Autodesk Fusion 360 part; units mm, degrees
(part 2 of 2)
extrude "124.5 mm pitch fan fixing clearance (3)" cut sketch "草图6 (8)" along normal blind 6 contours A0 in plane through (0, -25, 0) normal (0, 1, 0) bodies 20 in component "10_GPU_140_FAN_MOUNT"
ref_plane "工作平面1" through (0, 25, 0) normal (0, 1, 0) x (0, 0, 1) in component "10_CPU_140_FAN_MOUNT"
sketch "草图1 (21)" plane through (0, 25, 0) normal (0, 1, 0) x (1, 0, 0) in component "10_CPU_140_FAN_MOUNT"
  line L0 (156.4, -210, -50) -> (296.4, -210, -50)
  line L1 (296.4, -210, -50) -> (296.4, -350, -50)
  line L2 (296.4, -350, -50) -> (156.4, -350, -50)
  line L3 (156.4, -350, -50) -> (156.4, -210, -50)
extrude "140 mm removable fan mounting frame'" add sketch "草图1 (21)" along normal blind 6 separate body contours L0 L1 L2 L3 in plane through (0, -25, 0) normal (0, 1, 0) makes body 21 in component "10_CPU_140_FAN_MOUNT"
ref_plane "工作平面2" through (0, 25, 0) normal (0, 1, 0) x (0, 0, 1) in component "10_CPU_140_FAN_MOUNT"
sketch "草图2 (17)" plane through (0, 25, 0) normal (0, 1, 0) x (1, 0, 0) in component "10_CPU_140_FAN_MOUNT"
  circle A0 through (291.4, -280, -50) (193.9, -223.7083, -50) (193.9, -336.2917, -50)
extrude "Open airflow aperture'" cut sketch "草图2 (17)" along normal blind 6 contours A0 in plane through (0, -25, 0) normal (0, 1, 0) bodies 21 in component "10_CPU_140_FAN_MOUNT"
ref_plane "工作平面3" through (0, 25, 0) normal (0, 1, 0) x (0, 0, 1) in component "10_CPU_140_FAN_MOUNT"
sketch "草图3 (13)" plane through (0, 25, 0) normal (0, 1, 0) x (1, 0, 0) in component "10_CPU_140_FAN_MOUNT"
  circle A0 through (166.4, -217.75, -50) (163.025, -215.8014, -50) (163.025, -219.6986, -50)
extrude "124.5 mm pitch fan fixing clearance'" cut sketch "草图3 (13)" along normal blind 6 contours A0 in plane through (0, -25, 0) normal (0, 1, 0) bodies 21 in component "10_CPU_140_FAN_MOUNT"
ref_plane "工作平面4" through (0, 25, 0) normal (0, 1, 0) x (0, 0, 1) in component "10_CPU_140_FAN_MOUNT"
sketch "草图4 (13)" plane through (0, 25, 0) normal (0, 1, 0) x (1, 0, 0) in component "10_CPU_140_FAN_MOUNT"
  circle A0 through (166.4, -342.25, -50) (163.025, -340.3014, -50) (163.025, -344.1986, -50)
extrude "124.5 mm pitch fan fixing clearance (1)'" cut sketch "草图4 (13)" along normal blind 6 contours A0 in plane through (0, -25, 0) normal (0, 1, 0) bodies 21 in component "10_CPU_140_FAN_MOUNT"
ref_plane "工作平面5" through (0, 25, 0) normal (0, 1, 0) x (0, 0, 1) in component "10_CPU_140_FAN_MOUNT"
sketch "草图5 (13)" plane through (0, 25, 0) normal (0, 1, 0) x (1, 0, 0) in component "10_CPU_140_FAN_MOUNT"
  circle A0 through (290.9, -217.75, -50) (287.525, -215.8014, -50) (287.525, -219.6986, -50)
extrude "124.5 mm pitch fan fixing clearance (2)'" cut sketch "草图5 (13)" along normal blind 6 contours A0 in plane through (0, -25, 0) normal (0, 1, 0) bodies 21 in component "10_CPU_140_FAN_MOUNT"
ref_plane "工作平面6" through (0, 25, 0) normal (0, 1, 0) x (0, 0, 1) in component "10_CPU_140_FAN_MOUNT"
sketch "草图6 (9)" plane through (0, 25, 0) normal (0, 1, 0) x (1, 0, 0) in component "10_CPU_140_FAN_MOUNT"
  circle A0 through (290.9, -342.25, -50) (287.525, -340.3014, -50) (287.525, -344.1986, -50)
extrude "124.5 mm pitch fan fixing clearance (3)'" cut sketch "草图6 (9)" along normal blind 6 contours A0 in plane through (0, -25, 0) normal (0, 1, 0) bodies 21 in component "10_CPU_140_FAN_MOUNT"
ref_plane "工作平面1" through (0, 50, 0) normal (0, 1, 0) x (0, 0, 1) in component "REF_CASE_FAN_GPU_140x140x25"
sketch "草图1 (22)" plane through (0, 50, 0) normal (0, 1, 0) x (1, 0, 0) in component "REF_CASE_FAN_GPU_140x140x25"
  line L0 (12.4, -210, -100) -> (152.4, -210, -100)
  line L1 (152.4, -210, -100) -> (152.4, -350, -100)
  line L2 (152.4, -350, -100) -> (12.4, -350, -100)
  line L3 (12.4, -350, -100) -> (12.4, -210, -100)
extrude "140x140x25 fan envelope" add sketch "草图1 (22)" along normal blind 25 separate body contours L0 L1 L2 L3 in plane through (0, -50, 0) normal (0, 1, 0) makes body 22 in component "REF_CASE_FAN_GPU_140x140x25"
ref_plane "工作平面2" through (0, 50, 0) normal (0, 1, 0) x (0, 0, 1) in component "REF_CASE_FAN_GPU_140x140x25"
sketch "草图2 (18)" plane through (0, 50, 0) normal (0, 1, 0) x (1, 0, 0) in component "REF_CASE_FAN_GPU_140x140x25"
  circle A0 through (147.4, -280, -100) (49.9, -223.7083, -100) (49.9, -336.2917, -100)
extrude "Rotor opening reference" cut sketch "草图2 (18)" along normal blind 25 contours A0 in plane through (0, -50, 0) normal (0, 1, 0) bodies 22 in component "REF_CASE_FAN_GPU_140x140x25"
ref_plane "工作平面3" through (0, 0, 278) normal (0, 0, 1) x (1, 0, 0) in component "REF_CASE_FAN_GPU_140x140x25"
sketch "草图3 (14)" plane through (0, 0, 278) normal (0, 0, 1) x (1, 0, 0) in component "REF_CASE_FAN_GPU_140x140x25"
  line L0 (15.4, -38) -> (149.4, -38)
  line L1 (149.4, -38) -> (149.4, -36)
  line L2 (149.4, -36) -> (15.4, -36)
  line L3 (15.4, -36) -> (15.4, -38)
extrude "Rotor reference spoke horizontal" add sketch "草图3 (14)" along normal blind 4 bodies 22 in component "REF_CASE_FAN_GPU_140x140x25"
ref_plane "工作平面4" through (0, 0, 213) normal (0, 0, 1) x (1, 0, 0) in component "REF_CASE_FAN_GPU_140x140x25"
sketch "草图4 (14)" plane through (0, 0, 213) normal (0, 0, 1) x (1, 0, 0) in component "REF_CASE_FAN_GPU_140x140x25"
  line L0 (80.4, -38) -> (84.4, -38)
  line L1 (84.4, -38) -> (84.4, -36)
  line L2 (84.4, -36) -> (80.4, -36)
  line L3 (80.4, -36) -> (80.4, -38)
extrude "Rotor reference spoke vertical" add sketch "草图4 (14)" along normal blind 134 bodies 22 in component "REF_CASE_FAN_GPU_140x140x25"
ref_plane "工作平面5" through (0, 38, 0) normal (0, 1, 0) x (0, 0, 1) in component "REF_CASE_FAN_GPU_140x140x25"
sketch "草图5 (14)" plane through (0, 38, 0) normal (0, 1, 0) x (1, 0, 0) in component "REF_CASE_FAN_GPU_140x140x25"
  circle A0 through (98.4, -280, -76) (74.4, -266.1436, -76) (74.4, -293.8564, -76)
extrude "Fan hub reference" add sketch "草图5 (14)" along normal blind 2 contours A0 in plane through (0, -38, 0) normal (0, 1, 0) bodies 22 in component "REF_CASE_FAN_GPU_140x140x25"
ref_plane "工作平面6" through (0, 50, 0) normal (0, 1, 0) x (0, 0, 1) in component "REF_CASE_FAN_GPU_140x140x25"
sketch "草图6 (10)" plane through (0, 50, 0) normal (0, 1, 0) x (1, 0, 0) in component "REF_CASE_FAN_GPU_140x140x25"
  circle A0 through (22.4, -217.75, -100) (19.025, -215.8014, -100) (19.025, -219.6986, -100)
extrude "Reference fan mounting bore" cut sketch "草图6 (10)" along normal blind 25 contours A0 in plane through (0, -50, 0) normal (0, 1, 0) bodies 22 in component "REF_CASE_FAN_GPU_140x140x25"
ref_plane "工作平面7" through (0, 50, 0) normal (0, 1, 0) x (0, 0, 1) in component "REF_CASE_FAN_GPU_140x140x25"
sketch "草图7 (7)" plane through (0, 50, 0) normal (0, 1, 0) x (1, 0, 0) in component "REF_CASE_FAN_GPU_140x140x25"
  circle A0 through (22.4, -342.25, -100) (19.025, -340.3014, -100) (19.025, -344.1986, -100)
extrude "Reference fan mounting bore (1)" cut sketch "草图7 (7)" along normal blind 25 contours A0 in plane through (0, -50, 0) normal (0, 1, 0) bodies 22 in component "REF_CASE_FAN_GPU_140x140x25"
ref_plane "工作平面8" through (0, 50, 0) normal (0, 1, 0) x (0, 0, 1) in component "REF_CASE_FAN_GPU_140x140x25"
sketch "草图8 (6)" plane through (0, 50, 0) normal (0, 1, 0) x (1, 0, 0) in component "REF_CASE_FAN_GPU_140x140x25"
  circle A0 through (146.9, -217.75, -100) (143.525, -215.8014, -100) (143.525, -219.6986, -100)
extrude "Reference fan mounting bore (2)" cut sketch "草图8 (6)" along normal blind 25 contours A0 in plane through (0, -50, 0) normal (0, 1, 0) bodies 22 in component "REF_CASE_FAN_GPU_140x140x25"
ref_plane "工作平面9" through (0, 50, 0) normal (0, 1, 0) x (0, 0, 1) in component "REF_CASE_FAN_GPU_140x140x25"
sketch "草图9 (6)" plane through (0, 50, 0) normal (0, 1, 0) x (1, 0, 0) in component "REF_CASE_FAN_GPU_140x140x25"
  circle A0 through (146.9, -342.25, -100) (143.525, -340.3014, -100) (143.525, -344.1986, -100)
extrude "Reference fan mounting bore (3)" cut sketch "草图9 (6)" along normal blind 25 contours A0 in plane through (0, -50, 0) normal (0, 1, 0) bodies 22 in component "REF_CASE_FAN_GPU_140x140x25"
ref_plane "工作平面1" through (0, 0, 279) normal (0, 0, 1) x (1, 0, 0) in component "REF_AIRFLOW_GPU_FRONT_TO_REAR"
sketch "草图1 (23)" plane through (0, 0, 279) normal (0, 0, 1) x (1, 0, 0) in component "REF_AIRFLOW_GPU_FRONT_TO_REAR"
  line L0 (77.4, -75) -> (87.4, -75)
  line L1 (87.4, -75) -> (87.4, -64)
  line L2 (87.4, -64) -> (94.4, -64)
  line L3 (94.4, -64) -> (82.4, -53)
  line L4 (82.4, -53) -> (70.4, -64)
  line L5 (70.4, -64) -> (77.4, -64)
  line L6 (77.4, -64) -> (77.4, -75)
extrude "Front intake direction +Y" add sketch "草图1 (23)" along normal blind 2 separate body makes body 23 in component "REF_AIRFLOW_GPU_FRONT_TO_REAR"
ref_plane "工作平面1" through (0, 50, 0) normal (0, 1, 0) x (0, 0, 1) in component "REF_CASE_FAN_CPU_140x140x25"
sketch "草图1 (24)" plane through (0, 50, 0) normal (0, 1, 0) x (1, 0, 0) in component "REF_CASE_FAN_CPU_140x140x25"
  line L0 (156.4, -210, -100) -> (296.4, -210, -100)
  line L1 (296.4, -210, -100) -> (296.4, -350, -100)
  line L2 (296.4, -350, -100) -> (156.4, -350, -100)
  line L3 (156.4, -350, -100) -> (156.4, -210, -100)
extrude "140x140x25 fan envelope'" add sketch "草图1 (24)" along normal blind 25 separate body contours L0 L1 L2 L3 in plane through (0, -50, 0) normal (0, 1, 0) makes body 24 in component "REF_CASE_FAN_CPU_140x140x25"
ref_plane "工作平面2" through (0, 50, 0) normal (0, 1, 0) x (0, 0, 1) in component "REF_CASE_FAN_CPU_140x140x25"
sketch "草图2 (19)" plane through (0, 50, 0) normal (0, 1, 0) x (1, 0, 0) in component "REF_CASE_FAN_CPU_140x140x25"
  circle A0 through (291.4, -280, -100) (193.9, -223.7083, -100) (193.9, -336.2917, -100)
extrude "Rotor opening reference'" cut sketch "草图2 (19)" along normal blind 25 contours A0 in plane through (0, -50, 0) normal (0, 1, 0) bodies 24 in component "REF_CASE_FAN_CPU_140x140x25"
ref_plane "工作平面3" through (0, 0, 278) normal (0, 0, 1) x (1, 0, 0) in component "REF_CASE_FAN_CPU_140x140x25"
sketch "草图3 (15)" plane through (0, 0, 278) normal (0, 0, 1) x (1, 0, 0) in component "REF_CASE_FAN_CPU_140x140x25"
  line L0 (159.4, -38) -> (293.4, -38)
  line L1 (293.4, -38) -> (293.4, -36)
  line L2 (293.4, -36) -> (159.4, -36)
  line L3 (159.4, -36) -> (159.4, -38)
extrude "Rotor reference spoke horizontal'" add sketch "草图3 (15)" along normal blind 4 bodies 24 in component "REF_CASE_FAN_CPU_140x140x25"
ref_plane "工作平面4" through (0, 0, 213) normal (0, 0, 1) x (1, 0, 0) in component "REF_CASE_FAN_CPU_140x140x25"
sketch "草图4 (15)" plane through (0, 0, 213) normal (0, 0, 1) x (1, 0, 0) in component "REF_CASE_FAN_CPU_140x140x25"
  line L0 (224.4, -38) -> (228.4, -38)
  line L1 (228.4, -38) -> (228.4, -36)
  line L2 (228.4, -36) -> (224.4, -36)
  line L3 (224.4, -36) -> (224.4, -38)
extrude "Rotor reference spoke vertical'" add sketch "草图4 (15)" along normal blind 134 bodies 24 in component "REF_CASE_FAN_CPU_140x140x25"
ref_plane "工作平面5" through (0, 38, 0) normal (0, 1, 0) x (0, 0, 1) in component "REF_CASE_FAN_CPU_140x140x25"
sketch "草图5 (15)" plane through (0, 38, 0) normal (0, 1, 0) x (1, 0, 0) in component "REF_CASE_FAN_CPU_140x140x25"
  circle A0 through (242.4, -280, -76) (218.4, -266.1436, -76) (218.4, -293.8564, -76)
extrude "Fan hub reference'" add sketch "草图5 (15)" along normal blind 2 contours A0 in plane through (0, -38, 0) normal (0, 1, 0) bodies 24 in component "REF_CASE_FAN_CPU_140x140x25"
ref_plane "工作平面6" through (0, 50, 0) normal (0, 1, 0) x (0, 0, 1) in component "REF_CASE_FAN_CPU_140x140x25"
sketch "草图6 (11)" plane through (0, 50, 0) normal (0, 1, 0) x (1, 0, 0) in component "REF_CASE_FAN_CPU_140x140x25"
  circle A0 through (166.4, -217.75, -100) (163.025, -215.8014, -100) (163.025, -219.6986, -100)
extrude "Reference fan mounting bore'" cut sketch "草图6 (11)" along normal blind 25 contours A0 in plane through (0, -50, 0) normal (0, 1, 0) bodies 24 in component "REF_CASE_FAN_CPU_140x140x25"
ref_plane "工作平面7" through (0, 50, 0) normal (0, 1, 0) x (0, 0, 1) in component "REF_CASE_FAN_CPU_140x140x25"
sketch "草图7 (8)" plane through (0, 50, 0) normal (0, 1, 0) x (1, 0, 0) in component "REF_CASE_FAN_CPU_140x140x25"
  circle A0 through (166.4, -342.25, -100) (163.025, -340.3014, -100) (163.025, -344.1986, -100)
extrude "Reference fan mounting bore (1)'" cut sketch "草图7 (8)" along normal blind 25 contours A0 in plane through (0, -50, 0) normal (0, 1, 0) bodies 24 in component "REF_CASE_FAN_CPU_140x140x25"
ref_plane "工作平面8" through (0, 50, 0) normal (0, 1, 0) x (0, 0, 1) in component "REF_CASE_FAN_CPU_140x140x25"
sketch "草图8 (7)" plane through (0, 50, 0) normal (0, 1, 0) x (1, 0, 0) in component "REF_CASE_FAN_CPU_140x140x25"
  circle A0 through (290.9, -217.75, -100) (287.525, -215.8014, -100) (287.525, -219.6986, -100)
extrude "Reference fan mounting bore (2)'" cut sketch "草图8 (7)" along normal blind 25 contours A0 in plane through (0, -50, 0) normal (0, 1, 0) bodies 24 in component "REF_CASE_FAN_CPU_140x140x25"
ref_plane "工作平面9" through (0, 50, 0) normal (0, 1, 0) x (0, 0, 1) in component "REF_CASE_FAN_CPU_140x140x25"
sketch "草图9 (7)" plane through (0, 50, 0) normal (0, 1, 0) x (1, 0, 0) in component "REF_CASE_FAN_CPU_140x140x25"
  circle A0 through (290.9, -342.25, -100) (287.525, -340.3014, -100) (287.525, -344.1986, -100)
extrude "Reference fan mounting bore (3)'" cut sketch "草图9 (7)" along normal blind 25 contours A0 in plane through (0, -50, 0) normal (0, 1, 0) bodies 24 in component "REF_CASE_FAN_CPU_140x140x25"
ref_plane "工作平面1" through (0, 0, 279) normal (0, 0, 1) x (1, 0, 0) in component "REF_AIRFLOW_CPU_FRONT_TO_REAR"
sketch "草图1 (25)" plane through (0, 0, 279) normal (0, 0, 1) x (1, 0, 0) in component "REF_AIRFLOW_CPU_FRONT_TO_REAR"
  line L0 (221.4, -75) -> (231.4, -75)
  line L1 (231.4, -75) -> (231.4, -64)
  line L2 (231.4, -64) -> (238.4, -64)
  line L3 (238.4, -64) -> (226.4, -53)
  line L4 (226.4, -53) -> (214.4, -64)
  line L5 (214.4, -64) -> (221.4, -64)
  line L6 (221.4, -64) -> (221.4, -75)
extrude "Front intake direction +Y'" add sketch "草图1 (25)" along normal blind 2 separate body makes body 25 in component "REF_AIRFLOW_CPU_FRONT_TO_REAR"
ref_plane "工作平面1" through (0, 0, 208) normal (0, 0, 1) x (1, 0, 0) in component "REF_BOARD_304.8x243.84_NUMBERED_HOLES"
sketch "草图1 (26)" plane through (0, 0, 208) normal (0, 0, 1) x (1, 0, 0) in component "REF_BOARD_304.8x243.84_NUMBERED_HOLES"
  line L0 (0, 0) -> (304.8, 0)
  line L1 (304.8, 0) -> (304.8, 243.84)
  line L2 (304.8, 243.84) -> (0, 243.84)
  line L3 (0, 243.84) -> (0, 0)
extrude "Motherboard component-side reference" add sketch "草图1 (26)" along normal blind 1.6 separate body makes body 26 in component "REF_BOARD_304.8x243.84_NUMBERED_HOLES"
ref_plane "工作平面2" through (0, 0, 208) normal (0, 0, 1) x (1, 0, 0) in component "REF_BOARD_304.8x243.84_NUMBERED_HOLES"
sketch "草图2 (20)" plane through (0, 0, 208) normal (0, 0, 1) x (1, 0, 0) in component "REF_BOARD_304.8x243.84_NUMBERED_HOLES"
  circle A0 centre (16.51, 233.68) radius 1.98
extrude "Board hole 1" cut sketch "草图2 (20)" along normal blind 1.6 bodies 26 in component "REF_BOARD_304.8x243.84_NUMBERED_HOLES"
ref_plane "工作平面3" through (0, 0, 208) normal (0, 0, 1) x (1, 0, 0) in component "REF_BOARD_304.8x243.84_NUMBERED_HOLES"
sketch "草图3 (16)" plane through (0, 0, 208) normal (0, 0, 1) x (1, 0, 0) in component "REF_BOARD_304.8x243.84_NUMBERED_HOLES"
  circle A0 centre (140.97, 233.68) radius 1.98
extrude "Board hole 2" cut sketch "草图3 (16)" along normal blind 1.6 bodies 26 in component "REF_BOARD_304.8x243.84_NUMBERED_HOLES"
ref_plane "工作平面4" through (0, 0, 208) normal (0, 0, 1) x (1, 0, 0) in component "REF_BOARD_304.8x243.84_NUMBERED_HOLES"
sketch "草图4 (16)" plane through (0, 0, 208) normal (0, 0, 1) x (1, 0, 0) in component "REF_BOARD_304.8x243.84_NUMBERED_HOLES"
  circle A0 centre (298.45, 210.82) radius 1.98
extrude "Board hole 3" cut sketch "草图4 (16)" along normal blind 1.6 bodies 26 in component "REF_BOARD_304.8x243.84_NUMBERED_HOLES"
ref_plane "工作平面5" through (0, 0, 208) normal (0, 0, 1) x (1, 0, 0) in component "REF_BOARD_304.8x243.84_NUMBERED_HOLES"
sketch "草图5 (16)" plane through (0, 0, 208) normal (0, 0, 1) x (1, 0, 0) in component "REF_BOARD_304.8x243.84_NUMBERED_HOLES"
  circle A0 centre (16.51, 78.74) radius 1.98
extrude "Board hole 4" cut sketch "草图5 (16)" along normal blind 1.6 bodies 26 in component "REF_BOARD_304.8x243.84_NUMBERED_HOLES"
ref_plane "工作平面6" through (0, 0, 208) normal (0, 0, 1) x (1, 0, 0) in component "REF_BOARD_304.8x243.84_NUMBERED_HOLES"
sketch "草图6 (12)" plane through (0, 0, 208) normal (0, 0, 1) x (1, 0, 0) in component "REF_BOARD_304.8x243.84_NUMBERED_HOLES"
  circle A0 centre (140.97, 78.74) radius 1.98
extrude "Board hole 5" cut sketch "草图6 (12)" along normal blind 1.6 bodies 26 in component "REF_BOARD_304.8x243.84_NUMBERED_HOLES"
ref_plane "工作平面7" through (0, 0, 208) normal (0, 0, 1) x (1, 0, 0) in component "REF_BOARD_304.8x243.84_NUMBERED_HOLES"
sketch "草图7 (9)" plane through (0, 0, 208) normal (0, 0, 1) x (1, 0, 0) in component "REF_BOARD_304.8x243.84_NUMBERED_HOLES"
  circle A0 centre (298.45, 78.74) radius 1.98
extrude "Board hole 6" cut sketch "草图7 (9)" along normal blind 1.6 bodies 26 in component "REF_BOARD_304.8x243.84_NUMBERED_HOLES"
ref_plane "工作平面8" through (0, 0, 208) normal (0, 0, 1) x (1, 0, 0) in component "REF_BOARD_304.8x243.84_NUMBERED_HOLES"
sketch "草图8 (8)" plane through (0, 0, 208) normal (0, 0, 1) x (1, 0, 0) in component "REF_BOARD_304.8x243.84_NUMBERED_HOLES"
  circle A0 centre (16.51, 6.35) radius 1.98
extrude "Board hole 7" cut sketch "草图8 (8)" along normal blind 1.6 bodies 26 in component "REF_BOARD_304.8x243.84_NUMBERED_HOLES"
ref_plane "工作平面9" through (0, 0, 208) normal (0, 0, 1) x (1, 0, 0) in component "REF_BOARD_304.8x243.84_NUMBERED_HOLES"
sketch "草图9 (8)" plane through (0, 0, 208) normal (0, 0, 1) x (1, 0, 0) in component "REF_BOARD_304.8x243.84_NUMBERED_HOLES"
  circle A0 centre (140.97, 6.35) radius 1.98
extrude "Board hole 8" cut sketch "草图9 (8)" along normal blind 1.6 bodies 26 in component "REF_BOARD_304.8x243.84_NUMBERED_HOLES"
ref_plane "工作平面10" through (0, 0, 208) normal (0, 0, 1) x (1, 0, 0) in component "REF_BOARD_304.8x243.84_NUMBERED_HOLES"
sketch "草图10 (4)" plane through (0, 0, 208) normal (0, 0, 1) x (1, 0, 0) in component "REF_BOARD_304.8x243.84_NUMBERED_HOLES"
  circle A0 centre (298.45, 6.35) radius 1.98
extrude "Board hole 9" cut sketch "草图10 (4)" along normal blind 1.6 bodies 26 in component "REF_BOARD_304.8x243.84_NUMBERED_HOLES"
ref_plane "工作平面1" through (0, 0, 209.6) normal (0, 0, 1) x (1, 0, 0) in component "REF_CPU_RIGHT"
sketch "草图1 (27)" plane through (0, 0, 209.6) normal (0, 0, 1) x (1, 0, 0) in component "REF_CPU_RIGHT"
  line L0 (185, 108.84) -> (260, 108.84)
  line L1 (260, 108.84) -> (260, 178.84)
  line L2 (260, 178.84) -> (185, 178.84)
  line L3 (185, 178.84) -> (185, 108.84)
extrude "CPU position reference only" add sketch "草图1 (27)" along normal blind 5 separate body makes body 27 in component "REF_CPU_RIGHT"
ref_plane "工作平面1" through (0, 0, 209.6) normal (0, 0, 1) x (1, 0, 0) in component "REF_MEMORY_RIGHT_FRONT"
sketch "草图1 (28)" plane through (0, 0, 209.6) normal (0, 0, 1) x (1, 0, 0) in component "REF_MEMORY_RIGHT_FRONT"
  line L0 (150, 57.24) -> (285, 57.24)
  line L1 (285, 57.24) -> (285, 62.44)
  line L2 (285, 62.44) -> (150, 62.44)
  line L3 (150, 62.44) -> (150, 57.24)
extrude "DIMM position reference" add sketch "草图1 (28)" along normal blind 12.4 separate body makes body 28 in component "REF_MEMORY_RIGHT_FRONT"
ref_plane "工作平面2" through (0, 0, 209.6) normal (0, 0, 1) x (1, 0, 0) in component "REF_MEMORY_RIGHT_FRONT"
sketch "草图2 (21)" plane through (0, 0, 209.6) normal (0, 0, 1) x (1, 0, 0) in component "REF_MEMORY_RIGHT_FRONT"
  line L0 (150, 47.24) -> (285, 47.24)
  line L1 (285, 47.24) -> (285, 52.44)
  line L2 (285, 52.44) -> (150, 52.44)
  line L3 (150, 52.44) -> (150, 47.24)
extrude "DIMM position reference (1)" add sketch "草图2 (21)" along normal blind 12.4 separate body makes body 29 in component "REF_MEMORY_RIGHT_FRONT"
ref_plane "工作平面3" through (0, 0, 209.6) normal (0, 0, 1) x (1, 0, 0) in component "REF_MEMORY_RIGHT_FRONT"
sketch "草图3 (17)" plane through (0, 0, 209.6) normal (0, 0, 1) x (1, 0, 0) in component "REF_MEMORY_RIGHT_FRONT"
  line L0 (150, 37.24) -> (285, 37.24)
  line L1 (285, 37.24) -> (285, 42.44)
  line L2 (285, 42.44) -> (150, 42.44)
  line L3 (150, 42.44) -> (150, 37.24)
extrude "DIMM position reference (2)" add sketch "草图3 (17)" along normal blind 12.4 separate body makes body 30 in component "REF_MEMORY_RIGHT_FRONT"
ref_plane "工作平面4" through (0, 0, 209.6) normal (0, 0, 1) x (1, 0, 0) in component "REF_MEMORY_RIGHT_FRONT"
sketch "草图4 (17)" plane through (0, 0, 209.6) normal (0, 0, 1) x (1, 0, 0) in component "REF_MEMORY_RIGHT_FRONT"
  line L0 (150, 27.24) -> (285, 27.24)
  line L1 (285, 27.24) -> (285, 32.44)
  line L2 (285, 32.44) -> (150, 32.44)
  line L3 (150, 32.44) -> (150, 27.24)
extrude "DIMM position reference (3)" add sketch "草图4 (17)" along normal blind 12.4 separate body makes body 31 in component "REF_MEMORY_RIGHT_FRONT"
ref_plane "工作平面1" through (0, 0, 209.6) normal (0, 0, 1) x (1, 0, 0) in component "REF_PRIMARY_PCIE_X126.4_APPROX"
sketch "草图1 (29)" plane through (0, 0, 209.6) normal (0, 0, 1) x (1, 0, 0) in component "REF_PRIMARY_PCIE_X126.4_APPROX"
  line L0 (122.4, 96.84) -> (130.4, 96.84)
  line L1 (130.4, 96.84) -> (130.4, 201.84)
  line L2 (130.4, 201.84) -> (122.4, 201.84)
  line L3 (122.4, 201.84) -> (122.4, 96.84)
extrude "Primary GPU slot approximate" add sketch "草图1 (29)" along normal blind 10 separate body makes body 32 in component "REF_PRIMARY_PCIE_X126.4_APPROX"
ref_plane "工作平面1" through (0, 0, 209.6) normal (0, 0, 1) x (1, 0, 0) in component "REF_SECOND_LONG_PCIE_X60_APPROX"
sketch "草图1 (30)" plane through (0, 0, 209.6) normal (0, 0, 1) x (1, 0, 0) in component "REF_SECOND_LONG_PCIE_X60_APPROX"
  line L0 (56, 96.84) -> (64, 96.84)
  line L1 (64, 96.84) -> (64, 201.84)
  line L2 (64, 201.84) -> (56, 201.84)
  line L3 (56, 201.84) -> (56, 96.84)
extrude "Second long PCIe approximate" add sketch "草图1 (30)" along normal blind 10 separate body makes body 33 in component "REF_SECOND_LONG_PCIE_X60_APPROX"
ref_plane "工作平面1" through (0, 0, 221) normal (0, 0, 1) x (1, 0, 0) in component "REF_GPU_FANS_TO_MINUS_X"
sketch "草图1 (31)" plane through (0, 0, 221) normal (0, 0, 1) x (1, 0, 0) in component "REF_GPU_FANS_TO_MINUS_X"
  line L0 (88.4, 20.84) -> (128.4, 20.84)
  line L1 (128.4, 20.84) -> (128.4, 243.84)
  line L2 (128.4, 243.84) -> (88.4, 243.84)
  line L3 (88.4, 243.84) -> (88.4, 20.84)
extrude "GPU body 40 x 223 x 114" add sketch "草图1 (31)" along normal blind 114 separate body makes body 34 in component "REF_GPU_FANS_TO_MINUS_X"
ref_plane "工作平面1" through (0, 0, 20) normal (0, 0, 1) x (1, 0, 0) in component "REF_PSU_CENTER_152.4_121.92"
sketch "草图1 (32)" plane through (0, 0, 20) normal (0, 0, 1) x (1, 0, 0) in component "REF_PSU_CENTER_152.4_121.92"
  line L0 (109.4, 51.92) -> (195.4, 51.92)
  line L1 (195.4, 51.92) -> (195.4, 191.92)
  line L2 (195.4, 191.92) -> (109.4, 191.92)
  line L3 (109.4, 191.92) -> (109.4, 51.92)
extrude "PSU 86 x 140 x 150" add sketch "草图1 (32)" along normal blind 150 separate body makes body 35 in component "REF_PSU_CENTER_152.4_121.92"
ref_plane "工作平面1" through (195.4, 0, 0) normal (1, 0, 0) x (0, 1, 0) in component "REF_PSU_INTAKE_PLUS_X_CPU_SIDE"
sketch "草图1 (33)" plane through (195.4, 0, 0) normal (1, 0, 0) x (0, 0, -1) in component "REF_PSU_INTAKE_PLUS_X_CPU_SIDE"
  circle A0 centre (-95, 121.92) radius 60
extrude "Large PSU intake fan faces CPU side" add sketch "草图1 (33)" along normal blind 0.3 separate body makes body 36 in component "REF_PSU_INTAKE_PLUS_X_CPU_SIDE"
ref_plane "工作平面1" through (88.1, 0, 0) normal (1, 0, 0) x (0, 1, 0) in component "REF_GPU_FAN_MARKERS_MINUS_X"
sketch "草图1 (34)" plane through (88.1, 0, 0) normal (1, 0, 0) x (0, 0, -1) in component "REF_GPU_FAN_MARKERS_MINUS_X"
  circle A0 centre (-278, 75) radius 46
extrude "GPU fan faces away from PSU fan" add sketch "草图1 (34)" along normal blind 0.3 separate body makes body 37 in component "REF_GPU_FAN_MARKERS_MINUS_X"
ref_plane "工作平面2" through (88.1, 0, 0) normal (1, 0, 0) x (0, 1, 0) in component "REF_GPU_FAN_MARKERS_MINUS_X"
sketch "草图2 (22)" plane through (88.1, 0, 0) normal (1, 0, 0) x (0, 0, -1) in component "REF_GPU_FAN_MARKERS_MINUS_X"
  circle A0 centre (-278, 180) radius 46
extrude "GPU fan faces away from PSU fan (1)" add sketch "草图2 (22)" along normal blind 0.3 separate body makes body 38 in component "REF_GPU_FAN_MARKERS_MINUS_X"
component "01_PCI_front_INSET_SIDE" placed x (1, 0, 0) y (0, 1, 0) z (0, 0, 1) at (0, 0, 0)
component "01_PCI_rear_INSET_SIDE" placed x (1, 0, 0) y (0, 1, 0) z (0, 0, 1) at (0, 0, 0)
component "01_CPU_front_VERTICAL_SIDE" placed x (1, 0, 0) y (0, 1, 0) z (0, 0, 1) at (0, 0, 0)
component "01_CPU_rear_VERTICAL_SIDE" placed x (1, 0, 0) y (0, 1, 0) z (0, 0, 1) at (0, 0, 0)
component "02_PCI_low_SEAM_PLATE" placed x (1, 0, 0) y (0, 1, 0) z (0, 0, 1) at (0, 0, 0)
component "02_PCI_high_SEAM_PLATE" placed x (1, 0, 0) y (0, 1, 0) z (0, 0, 1) at (0, 0, 0)
component "02_CPU_low_SEAM_PLATE" placed x (1, 0, 0) y (0, 1, 0) z (0, 0, 1) at (0, 0, 0)
component "02_CPU_high_SEAM_PLATE" placed x (1, 0, 0) y (0, 1, 0) z (0, 0, 1) at (0, 0, 0)
component "03_FRONT_MOTHERBOARD_BEAM" placed x (1, 0, 0) y (0, 1, 0) z (0, 0, 1) at (0, 0, 0)
component "03_MID_MOTHERBOARD_BEAM" placed x (1, 0, 0) y (0, 1, 0) z (0, 0, 1) at (0, 0, 0)
component "03_REAR_MOTHERBOARD_BEAM" placed x (1, 0, 0) y (0, 1, 0) z (0, 0, 1) at (0, 0, 0)
component "04_front_GROUND_BAR_290mm" placed x (1, 0, 0) y (0, 1, 0) z (0, 0, 1) at (0, 0, 0)
component "04_rear_GROUND_BAR_290mm" placed x (1, 0, 0) y (0, 1, 0) z (0, 0, 1) at (0, 0, 0)
component "05_CENTERED_PSU_CRADLE" placed x (1, 0, 0) y (0, 1, 0) z (0, 0, 1) at (0, 0, 0)
component "06_PCI_PSU_RETAINER" placed x (1, 0, 0) y (0, 1, 0) z (0, 0, 1) at (0, 0, 0)
component "06_CPU_PSU_RETAINER" placed x (1, 0, 0) y (0, 1, 0) z (0, 0, 1) at (0, 0, 0)
component "07_GPU_REAR_TOWER" placed x (1, 0, 0) y (0, 1, 0) z (0, 0, 1) at (0, 0, 0)
component "08_GPU_REAR_SLIDER" placed x (1, 0, 0) y (0, 1, 0) z (0, 0, 1) at (0, 0, 0)
component "09_FRONT_DUAL_FAN_CARRIER" placed x (1, 0, 0) y (0, 1, 0) z (0, 0, 1) at (0, 0, 0)
component "10_GPU_140_FAN_MOUNT" placed x (1, 0, 0) y (0, 1, 0) z (0, 0, 1) at (0, 0, 0)
component "10_CPU_140_FAN_MOUNT" placed x (1, 0, 0) y (0, 1, 0) z (0, 0, 1) at (0, 0, 0)
component "REF_CASE_FAN_GPU_140x140x25" placed x (1, 0, 0) y (0, 1, 0) z (0, 0, 1) at (0, 0, 0)
component "REF_AIRFLOW_GPU_FRONT_TO_REAR" placed x (1, 0, 0) y (0, 1, 0) z (0, 0, 1) at (0, 0, 0)
component "REF_CASE_FAN_CPU_140x140x25" placed x (1, 0, 0) y (0, 1, 0) z (0, 0, 1) at (0, 0, 0)
component "REF_AIRFLOW_CPU_FRONT_TO_REAR" placed x (1, 0, 0) y (0, 1, 0) z (0, 0, 1) at (0, 0, 0)
component "REF_BOARD_304.8x243.84_NUMBERED_HOLES" placed x (1, 0, 0) y (0, 1, 0) z (0, 0, 1) at (0, 0, 0)
component "REF_CPU_RIGHT" placed x (1, 0, 0) y (0, 1, 0) z (0, 0, 1) at (0, 0, 0)
component "REF_MEMORY_RIGHT_FRONT" placed x (1, 0, 0) y (0, 1, 0) z (0, 0, 1) at (0, 0, 0)
component "REF_PRIMARY_PCIE_X126.4_APPROX" placed x (1, 0, 0) y (0, 1, 0) z (0, 0, 1) at (0, 0, 0)
component "REF_SECOND_LONG_PCIE_X60_APPROX" placed x (1, 0, 0) y (0, 1, 0) z (0, 0, 1) at (0, 0, 0)
component "REF_GPU_FANS_TO_MINUS_X" placed x (1, 0, 0) y (0, 1, 0) z (0, 0, 1) at (0, 0, 0)
component "REF_PSU_CENTER_152.4_121.92" placed x (1, 0, 0) y (0, 1, 0) z (0, 0, 1) at (0, 0, 0)
component "REF_PSU_INTAKE_PLUS_X_CPU_SIDE" placed x (1, 0, 0) y (0, 1, 0) z (0, 0, 1) at (0, 0, 0)
component "REF_GPU_FAN_MARKERS_MINUS_X" placed x (1, 0, 0) y (0, 1, 0) z (0, 0, 1) at (0, 0, 0)
equation "desk_limit = 290 mm" comment "V03 layout review; fixed profiles require regeneration"
equation "footprint_width = 290 mm" comment "V03 layout review; fixed profiles require regeneration"
equation "board_width = 304.8 mm" comment "V03 layout review; fixed profiles require regeneration"
equation "board_depth = 243.84 mm" comment "V03 layout review; fixed profiles require regeneration"
equation "board_bottom_height = 208 mm" comment "V03 layout review; fixed profiles require regeneration"
equation "approx_slot_x = 126.4 mm" comment "V03 layout review; fixed profiles require regeneration"
